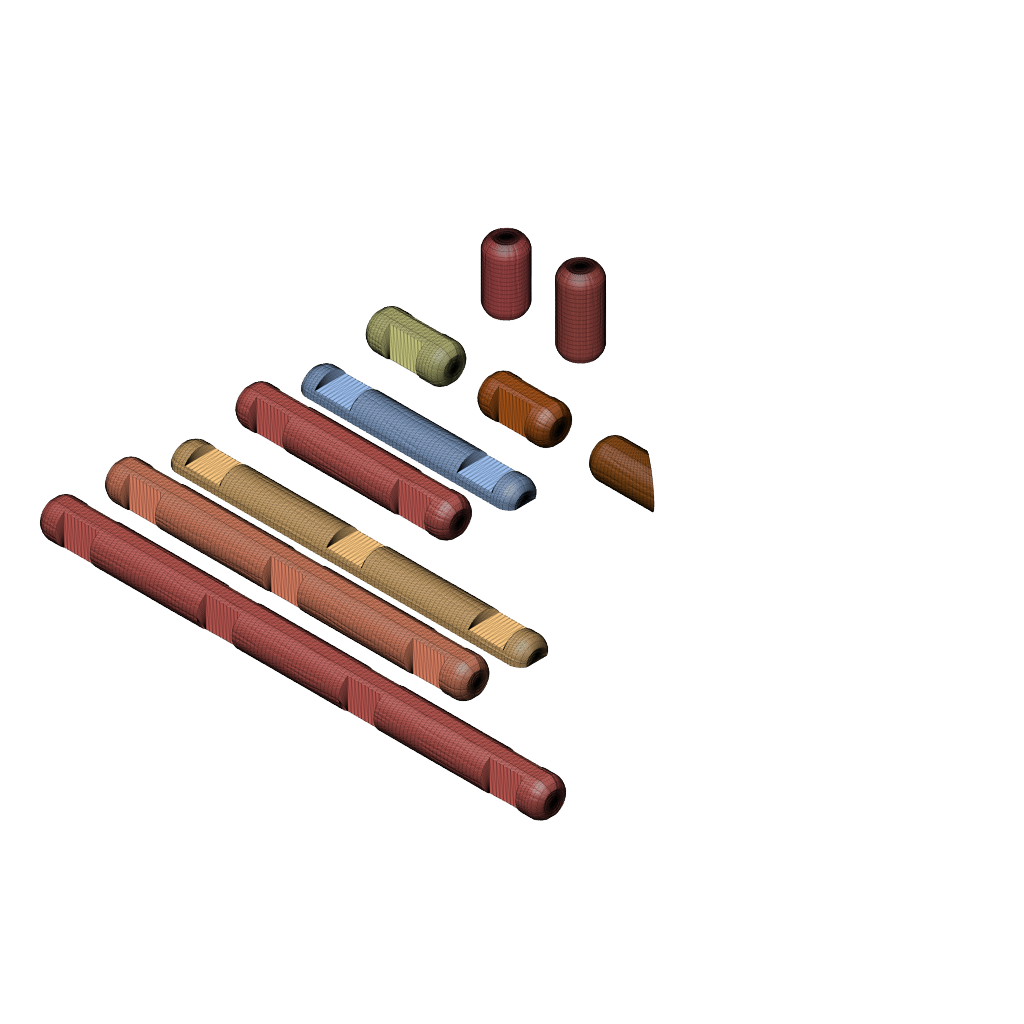
DeadPresidentTreeSections_ball_end_round (Autodesk Fusion 360 design; units mm, degrees)
part number: 2026-11-17-20-53-16-767
part number: 2026-11-17-20-53-16-854
part number: 2026-11-17-20-53-17-063
part number: 2026-11-17-20-53-17-313
part number: 2026-11-17-20-53-17-579
part number: 2026-11-17-20-53-17-888
part number: 2026-11-17-20-53-18-275
part number: 2026-11-17-20-53-18-680
part number: 2026-11-17-20-53-19-149
part number: 2026-11-17-20-53-19-560
part number: 2026-11-17-20-53-19-708
Autodesk Fusion 360 part; units mm, degrees
sketch "Section" plane through (0, 0, 0) normal (1, 0, 0) x (0, 0, -1) in component "log_1insert_1-5_8_rounded"
  circle A0 centre (-9.125, 0) radius 9.525
  dimension "d15" = 9.125
  dimension "d16" = 19.05
  constraint horizontal origin A0.centre
  measures "d15" horizontal distance of origin A0.centre
  measures "d16" diameter of A0
extrude "Log" add sketch "Section" along normal blind 41.275 makes body 1 in component "log_1insert_1-5_8_rounded"
fillet "Rounded ends" radius 4 2 edges at (41.275, -3.4444, 18.0054) (0, -3.4444, 18.0054) on bodies 1 in component "log_1insert_1-5_8_rounded"
sketch "Flats" plane through (0, 0, 0) normal (1, 0, 0) x (0, 0, -1) in component "log_1insert_1-5_8_rounded"
  line L0 (0.8, -11.525) -> (0.8, 11.525)
  line L1 (0.8, 11.525) -> (0, 11.525)
  line L2 (0, 11.525) -> (0, -11.525)
  line L3 (0, -11.525) -> (0.8, -11.525)
  line L4 (-18.25, -11.525) -> (-18.25, 11.525)
  line L5 (-18.25, 11.525) -> (-20.05, 11.525)
  line L6 (-20.05, 11.525) -> (-20.05, -11.525)
  line L7 (-20.05, -11.525) -> (-18.25, -11.525)
  dimension "d21" = 11.525
  dimension "d22" = 0.8
  dimension "d23" = 11.525
  dimension "d24" = 11.525
  dimension "d25" = 18.25
  dimension "d26" = 11.525
  dimension "d27" = 20.05
  constraint vertical L0
  constraint horizontal L1
  constraint vertical L2
  constraint horizontal L3
  constraint vertical origin L1.end
  constraint vertical L4
  constraint horizontal L5
  constraint vertical L6
  constraint horizontal L7
  measures "d21" vertical distance of origin L0.start
  measures "d22" horizontal distance of origin L0.start
  measures "d23" vertical distance of origin L1.end
  measures "d24" vertical distance of origin L4.start
  measures "d25" horizontal distance of origin L4.start
  measures "d26" vertical distance of origin L5.end
  measures "d27" horizontal distance of origin L5.end
extrude "Flats (1)" cut sketch "Flats" along normal blind 41.275 bodies 1 in component "log_1insert_1-5_8_rounded"
sketch "Notch" plane through (0, 0, 0) normal (0, 0, 1) x (1, 0, 0) in component "log_1insert_1-5_8_rounded"
  line L0 (11.3125, 4.7625) -> (29.9625, 4.7625)
  line L1 (29.9625, 4.7625) -> (29.9625, 11.525)
  line L2 (29.9625, 11.525) -> (11.3125, 11.525)
  line L3 (11.3125, 11.525) -> (11.3125, 4.7625)
  line L4 (11.3125, -4.7625) -> (29.9625, -4.7625)
  line L5 (29.9625, -4.7625) -> (29.9625, -11.525)
  line L6 (29.9625, -11.525) -> (11.3125, -11.525)
  line L7 (11.3125, -11.525) -> (11.3125, -4.7625)
  dimension "d30" = 11.3125
  dimension "d31" = 4.7625
  dimension "d32" = 29.9625
  dimension "d33" = 11.525
  dimension "d34" = 11.3125
  dimension "d35" = 4.7625
  dimension "d36" = 29.9625
  dimension "d37" = 11.525
  constraint horizontal L0
  constraint vertical L1
  constraint horizontal L2
  constraint vertical L3
  constraint horizontal L4
  constraint vertical L5
  constraint horizontal L6
  constraint vertical L7
  measures "d30" horizontal distance of origin L0.start
  measures "d31" vertical distance of origin L0.start
  measures "d32" horizontal distance of origin L1.end
  measures "d33" vertical distance of origin L1.end
  measures "d34" horizontal distance of origin L4.start
  measures "d35" vertical distance of origin L4.start
  measures "d36" horizontal distance of origin L5.end
  measures "d37" vertical distance of origin L5.end
extrude "Notch cut" cut sketch "Notch" along normal blind 21.05 bodies 1 in component "log_1insert_1-5_8_rounded"
pattern_linear "Notch pattern" count 2 spacing 0.001 along (1, 0, 0) count 3 spacing 0 along (1, 0, 0) of "Notch cut" in component "log_1insert_1-5_8_rounded"
other "Base Mesh Feature1" in component "log_1insert_1-5_8_rounded"
sketch "Section (2)" plane through (0, 0, 0) normal (1, 0, 0) x (0, 0, -1) in component "log_1insert_1-1_2_round_rounded"
  circle A0 centre (-9.125, 0) radius 9.525
  dimension "d48" = 9.125
  dimension "d49" = 19.05
  constraint horizontal origin A0.centre
  measures "d48" horizontal distance of origin A0.centre
  measures "d49" diameter of A0
extrude "Log'" add sketch "Section (2)" along normal blind 38.1 separate body makes body 2 in component "log_1insert_1-1_2_round_rounded"
fillet "Rounded ends'" radius 4 2 edges at (38.1, -3.4444, 18.0054) (0, -3.4444, 18.0054) on bodies 2 in component "log_1insert_1-1_2_round_rounded"
sketch "Flats (2)" plane through (0, 0, 0) normal (1, 0, 0) x (0, 0, -1) in component "log_1insert_1-1_2_round_rounded"
  line L0 (0.8, -11.525) -> (0.8, 11.525)
  line L1 (0.8, 11.525) -> (0, 11.525)
  line L2 (0, 11.525) -> (0, -11.525)
  line L3 (0, -11.525) -> (0.8, -11.525)
  line L4 (-18.25, -11.525) -> (-18.25, 11.525)
  line L5 (-18.25, 11.525) -> (-20.05, 11.525)
  line L6 (-20.05, 11.525) -> (-20.05, -11.525)
  line L7 (-20.05, -11.525) -> (-18.25, -11.525)
  dimension "d54" = 11.525
  dimension "d55" = 0.8
  dimension "d56" = 11.525
  dimension "d57" = 11.525
  dimension "d58" = 18.25
  dimension "d59" = 11.525
  dimension "d60" = 20.05
  constraint vertical L0
  constraint horizontal L1
  constraint vertical L2
  constraint horizontal L3
  constraint vertical origin L1.end
  constraint vertical L4
  constraint horizontal L5
  constraint vertical L6
  constraint horizontal L7
  measures "d54" vertical distance of origin L0.start
  measures "d55" horizontal distance of origin L0.start
  measures "d56" vertical distance of origin L1.end
  measures "d57" vertical distance of origin L4.start
  measures "d58" horizontal distance of origin L4.start
  measures "d59" vertical distance of origin L5.end
  measures "d60" horizontal distance of origin L5.end
extrude "Flats (1)'" cut sketch "Flats (2)" along normal blind 38.1 bodies 2 in component "log_1insert_1-1_2_round_rounded"
sketch "Notch (2)" plane through (0, 0, 0) normal (0, 0, 1) x (1, 0, 0) in component "log_1insert_1-1_2_round_rounded"
  line L0 (9.725, 4.7625) -> (28.375, 4.7625)
  line L1 (28.375, 4.7625) -> (28.375, 11.525)
  line L2 (28.375, 11.525) -> (9.725, 11.525)
  line L3 (9.725, 11.525) -> (9.725, 4.7625)
  line L4 (9.725, -4.7625) -> (28.375, -4.7625)
  line L5 (28.375, -4.7625) -> (28.375, -11.525)
  line L6 (28.375, -11.525) -> (9.725, -11.525)
  line L7 (9.725, -11.525) -> (9.725, -4.7625)
  dimension "d63" = 9.725
  dimension "d64" = 4.7625
  dimension "d65" = 28.375
  dimension "d66" = 11.525
  dimension "d67" = 9.725
  dimension "d68" = 4.7625
  dimension "d69" = 28.375
  dimension "d70" = 11.525
  constraint horizontal L0
  constraint vertical L1
  constraint horizontal L2
  constraint vertical L3
  constraint horizontal L4
  constraint vertical L5
  constraint horizontal L6
  constraint vertical L7
  measures "d63" horizontal distance of origin L0.start
  measures "d64" vertical distance of origin L0.start
  measures "d65" horizontal distance of origin L1.end
  measures "d66" vertical distance of origin L1.end
  measures "d67" horizontal distance of origin L4.start
  measures "d68" vertical distance of origin L4.start
  measures "d69" horizontal distance of origin L5.end
  measures "d70" vertical distance of origin L5.end
extrude "Notch cut'" cut sketch "Notch (2)" along normal blind 21.05 bodies 2 in component "log_1insert_1-1_2_round_rounded"
pattern_linear "Notch pattern'" count 2 spacing 0.001 along (1, 0, 0) count 3 spacing 0 along (1, 0, 0) of "Notch cut'" in component "log_1insert_1-1_2_round_rounded"
other "Base Mesh Feature1'" in component "log_1insert_1-1_2_round_rounded"
sketch "Section (3)" plane through (0, 0, 0) normal (1, 0, 0) x (0, 0, -1) in component "log_2insert_4-1_2_rounded"
  circle A0 centre (-9.125, 0) radius 9.525
  dimension "d81" = 9.125
  dimension "d82" = 19.05
  constraint horizontal origin A0.centre
  measures "d81" horizontal distance of origin A0.centre
  measures "d82" diameter of A0
extrude "Log''" add sketch "Section (3)" along normal blind 114.3 separate body makes body 3 in component "log_2insert_4-1_2_rounded"
fillet "Rounded ends''" radius 4 2 edges at (114.3, -3.4444, 18.0054) (0, -3.4444, 18.0054) on bodies 3 in component "log_2insert_4-1_2_rounded"
sketch "Flats (3)" plane through (0, 0, 0) normal (1, 0, 0) x (0, 0, -1) in component "log_2insert_4-1_2_rounded"
  line L0 (0.8, -11.525) -> (0.8, 11.525)
  line L1 (0.8, 11.525) -> (0, 11.525)
  line L2 (0, 11.525) -> (0, -11.525)
  line L3 (0, -11.525) -> (0.8, -11.525)
  line L4 (-18.25, -11.525) -> (-18.25, 11.525)
  line L5 (-18.25, 11.525) -> (-20.05, 11.525)
  line L6 (-20.05, 11.525) -> (-20.05, -11.525)
  line L7 (-20.05, -11.525) -> (-18.25, -11.525)
  dimension "d87" = 11.525
  dimension "d88" = 0.8
  dimension "d89" = 11.525
  dimension "d90" = 11.525
  dimension "d91" = 18.25
  dimension "d92" = 11.525
  dimension "d93" = 20.05
  constraint vertical L0
  constraint horizontal L1
  constraint vertical L2
  constraint horizontal L3
  constraint vertical origin L1.end
  constraint vertical L4
  constraint horizontal L5
  constraint vertical L6
  constraint horizontal L7
  measures "d87" vertical distance of origin L0.start
  measures "d88" horizontal distance of origin L0.start
  measures "d89" vertical distance of origin L1.end
  measures "d90" vertical distance of origin L4.start
  measures "d91" horizontal distance of origin L4.start
  measures "d92" vertical distance of origin L5.end
  measures "d93" horizontal distance of origin L5.end
extrude "Flats (1)''" cut sketch "Flats (3)" along normal blind 114.3 bodies 3 in component "log_2insert_4-1_2_rounded"
sketch "Notch (3)" plane through (0, 0, 0) normal (0, 0, 1) x (1, 0, 0) in component "log_2insert_4-1_2_rounded"
  line L0 (9.725, 4.7625) -> (28.375, 4.7625)
  line L1 (28.375, 4.7625) -> (28.375, 11.525)
  line L2 (28.375, 11.525) -> (9.725, 11.525)
  line L3 (9.725, 11.525) -> (9.725, 4.7625)
  line L4 (9.725, -4.7625) -> (28.375, -4.7625)
  line L5 (28.375, -4.7625) -> (28.375, -11.525)
  line L6 (28.375, -11.525) -> (9.725, -11.525)
  line L7 (9.725, -11.525) -> (9.725, -4.7625)
  dimension "d96" = 9.725
  dimension "d97" = 4.7625
  dimension "d98" = 28.375
  dimension "d99" = 11.525
  dimension "d100" = 9.725
  dimension "d101" = 4.7625
  dimension "d102" = 28.375
  dimension "d103" = 11.525
  constraint horizontal L0
  constraint vertical L1
  constraint horizontal L2
  constraint vertical L3
  constraint horizontal L4
  constraint vertical L5
  constraint horizontal L6
  constraint vertical L7
  measures "d96" horizontal distance of origin L0.start
  measures "d97" vertical distance of origin L0.start
  measures "d98" horizontal distance of origin L1.end
  measures "d99" vertical distance of origin L1.end
  measures "d100" horizontal distance of origin L4.start
  measures "d101" vertical distance of origin L4.start
  measures "d102" horizontal distance of origin L5.end
  measures "d103" vertical distance of origin L5.end
extrude "Notch cut''" cut sketch "Notch (3)" along normal blind 21.05 bodies 3 in component "log_2insert_4-1_2_rounded"
pattern_linear "Notch pattern''" count 2 spacing 76.2 along (1, 0, 0) count 3 spacing 0 along (1, 0, 0) of "Notch cut''" in component "log_2insert_4-1_2_rounded"
other "Base Mesh Feature1''" in component "log_2insert_4-1_2_rounded"
sketch "Section (4)" plane through (0, 0, 0) normal (1, 0, 0) x (0, 0, -1) in component "log_3insert_7-5_8_rounded"
  circle A0 centre (-9.125, 0) radius 9.525
  dimension "d114" = 9.125
  dimension "d115" = 19.05
  constraint horizontal origin A0.centre
  measures "d114" horizontal distance of origin A0.centre
  measures "d115" diameter of A0
extrude "Log'''" add sketch "Section (4)" along normal blind 193.675 separate body makes body 4 in component "log_3insert_7-5_8_rounded"
fillet "Rounded ends'''" radius 4 2 edges at (193.675, -3.4444, 18.0054) (0, -3.4444, 18.0054) on bodies 4 in component "log_3insert_7-5_8_rounded"
sketch "Flats (4)" plane through (0, 0, 0) normal (1, 0, 0) x (0, 0, -1) in component "log_3insert_7-5_8_rounded"
  line L0 (0.8, -11.525) -> (0.8, 11.525)
  line L1 (0.8, 11.525) -> (0, 11.525)
  line L2 (0, 11.525) -> (0, -11.525)
  line L3 (0, -11.525) -> (0.8, -11.525)
  line L4 (-18.25, -11.525) -> (-18.25, 11.525)
  line L5 (-18.25, 11.525) -> (-20.05, 11.525)
  line L6 (-20.05, 11.525) -> (-20.05, -11.525)
  line L7 (-20.05, -11.525) -> (-18.25, -11.525)
  dimension "d120" = 11.525
  dimension "d121" = 0.8
  dimension "d122" = 11.525
  dimension "d123" = 11.525
  dimension "d124" = 18.25
  dimension "d125" = 11.525
  dimension "d126" = 20.05
  constraint vertical L0
  constraint horizontal L1
  constraint vertical L2
  constraint horizontal L3
  constraint vertical origin L1.end
  constraint vertical L4
  constraint horizontal L5
  constraint vertical L6
  constraint horizontal L7
  measures "d120" vertical distance of origin L0.start
  measures "d121" horizontal distance of origin L0.start
  measures "d122" vertical distance of origin L1.end
  measures "d123" vertical distance of origin L4.start
  measures "d124" horizontal distance of origin L4.start
  measures "d125" vertical distance of origin L5.end
  measures "d126" horizontal distance of origin L5.end
extrude "Flats (1)'''" cut sketch "Flats (4)" along normal blind 193.675 bodies 4 in component "log_3insert_7-5_8_rounded"
sketch "Notch (4)" plane through (0, 0, 0) normal (0, 0, 1) x (1, 0, 0) in component "log_3insert_7-5_8_rounded"
  line L0 (11.3125, 4.7625) -> (29.9625, 4.7625)
  line L1 (29.9625, 4.7625) -> (29.9625, 11.525)
  line L2 (29.9625, 11.525) -> (11.3125, 11.525)
  line L3 (11.3125, 11.525) -> (11.3125, 4.7625)
  line L4 (11.3125, -4.7625) -> (29.9625, -4.7625)
  line L5 (29.9625, -4.7625) -> (29.9625, -11.525)
  line L6 (29.9625, -11.525) -> (11.3125, -11.525)
  line L7 (11.3125, -11.525) -> (11.3125, -4.7625)
  dimension "d129" = 11.3125
  dimension "d130" = 4.7625
  dimension "d131" = 29.9625
  dimension "d132" = 11.525
  dimension "d133" = 11.3125
  dimension "d134" = 4.7625
  dimension "d135" = 29.9625
  dimension "d136" = 11.525
  constraint horizontal L0
  constraint vertical L1
  constraint horizontal L2
  constraint vertical L3
  constraint horizontal L4
  constraint vertical L5
  constraint horizontal L6
  constraint vertical L7
  measures "d129" horizontal distance of origin L0.start
  measures "d130" vertical distance of origin L0.start
  measures "d131" horizontal distance of origin L1.end
  measures "d132" vertical distance of origin L1.end
  measures "d133" horizontal distance of origin L4.start
  measures "d134" vertical distance of origin L4.start
  measures "d135" horizontal distance of origin L5.end
  measures "d136" vertical distance of origin L5.end
extrude "Notch cut'''" cut sketch "Notch (4)" along normal blind 21.05 bodies 4 in component "log_3insert_7-5_8_rounded"
pattern_linear "Notch pattern'''" count 3 spacing 76.2 along (1, 0, 0) count 3 spacing 0 along (1, 0, 0) of "Notch cut'''" in component "log_3insert_7-5_8_rounded"
other "Base Mesh Feature1'''" in component "log_3insert_7-5_8_rounded"
sketch "Section (5)" plane through (0, 0, 0) normal (1, 0, 0) x (0, 0, -1) in component "log_4insert_10-5_8_rounded"
  circle A0 centre (-9.125, 0) radius 9.525
  dimension "d147" = 9.125
  dimension "d148" = 19.05
  constraint horizontal origin A0.centre
  measures "d147" horizontal distance of origin A0.centre
  measures "d148" diameter of A0
extrude "Log''''" add sketch "Section (5)" along normal blind 269.875 separate body makes body 5 in component "log_4insert_10-5_8_rounded"
fillet "Rounded ends''''" radius 4 2 edges at (269.875, -3.4444, 18.0054) (0, -3.4444, 18.0054) on bodies 5 in component "log_4insert_10-5_8_rounded"
sketch "Flats (5)" plane through (0, 0, 0) normal (1, 0, 0) x (0, 0, -1) in component "log_4insert_10-5_8_rounded"
  line L0 (0.8, -11.525) -> (0.8, 11.525)
  line L1 (0.8, 11.525) -> (0, 11.525)
  line L2 (0, 11.525) -> (0, -11.525)
  line L3 (0, -11.525) -> (0.8, -11.525)
  line L4 (-18.25, -11.525) -> (-18.25, 11.525)
  line L5 (-18.25, 11.525) -> (-20.05, 11.525)
  line L6 (-20.05, 11.525) -> (-20.05, -11.525)
  line L7 (-20.05, -11.525) -> (-18.25, -11.525)
  dimension "d153" = 11.525
  dimension "d154" = 0.8
  dimension "d155" = 11.525
  dimension "d156" = 11.525
  dimension "d157" = 18.25
  dimension "d158" = 11.525
  dimension "d159" = 20.05
  constraint vertical L0
  constraint horizontal L1
  constraint vertical L2
  constraint horizontal L3
  constraint vertical origin L1.end
  constraint vertical L4
  constraint horizontal L5
  constraint vertical L6
  constraint horizontal L7
  measures "d153" vertical distance of origin L0.start
  measures "d154" horizontal distance of origin L0.start
  measures "d155" vertical distance of origin L1.end
  measures "d156" vertical distance of origin L4.start
  measures "d157" horizontal distance of origin L4.start
  measures "d158" vertical distance of origin L5.end
  measures "d159" horizontal distance of origin L5.end
extrude "Flats (1)''''" cut sketch "Flats (5)" along normal blind 269.875 bodies 5 in component "log_4insert_10-5_8_rounded"
sketch "Notch (5)" plane through (0, 0, 0) normal (0, 0, 1) x (1, 0, 0) in component "log_4insert_10-5_8_rounded"
  line L0 (11.3125, 4.7625) -> (29.9625, 4.7625)
  line L1 (29.9625, 4.7625) -> (29.9625, 11.525)
  line L2 (29.9625, 11.525) -> (11.3125, 11.525)
  line L3 (11.3125, 11.525) -> (11.3125, 4.7625)
  line L4 (11.3125, -4.7625) -> (29.9625, -4.7625)
  line L5 (29.9625, -4.7625) -> (29.9625, -11.525)
  line L6 (29.9625, -11.525) -> (11.3125, -11.525)
  line L7 (11.3125, -11.525) -> (11.3125, -4.7625)
  dimension "d162" = 11.3125
  dimension "d163" = 4.7625
  dimension "d164" = 29.9625
  dimension "d165" = 11.525
  dimension "d166" = 11.3125
  dimension "d167" = 4.7625
  dimension "d168" = 29.9625
  dimension "d169" = 11.525
  constraint horizontal L0
  constraint vertical L1
  constraint horizontal L2
  constraint vertical L3
  constraint horizontal L4
  constraint vertical L5
  constraint horizontal L6
  constraint vertical L7
  measures "d162" horizontal distance of origin L0.start
  measures "d163" vertical distance of origin L0.start
  measures "d164" horizontal distance of origin L1.end
  measures "d165" vertical distance of origin L1.end
  measures "d166" horizontal distance of origin L4.start
  measures "d167" vertical distance of origin L4.start
  measures "d168" horizontal distance of origin L5.end
  measures "d169" vertical distance of origin L5.end
extrude "Notch cut''''" cut sketch "Notch (5)" along normal blind 21.05 bodies 5 in component "log_4insert_10-5_8_rounded"
pattern_linear "Notch pattern''''" count 4 spacing 76.2 along (1, 0, 0) count 3 spacing 0 along (1, 0, 0) of "Notch cut''''" in component "log_4insert_10-5_8_rounded"
other "Base Mesh Feature1''''" in component "log_4insert_10-5_8_rounded"
sketch "Section (6)" plane through (0, 0, 0) normal (1, 0, 0) x (0, 0, -1) in component "base_log_4-1_2_rounded"
  circle A0 centre (0, 0) radius 9.525
  dimension "d180" = 19.05
  constraint coincident A0.centre origin
  measures "d180" diameter of A0
extrude "Log'''''" add sketch "Section (6)" along normal blind 114.3 separate body makes body 6 in component "base_log_4-1_2_rounded"
fillet "Rounded ends'''''" radius 4 2 edges at (114.3, -3.4444, 8.8804) (0, -3.4444, 8.8804) on bodies 6 in component "base_log_4-1_2_rounded"
sketch "Bed and side flats" plane through (0, 0, 0) normal (1, 0, 0) x (0, 0, -1) in component "base_log_4-1_2_rounded"
  line L0 (10.525, -11.525) -> (10.525, 11.525)
  line L1 (10.525, 11.525) -> (0, 11.525)
  line L2 (0, 11.525) -> (0, -11.525)
  line L3 (0, -11.525) -> (10.525, -11.525)
  line L4 (1, 9.125) -> (1, 11.525)
  line L5 (1, 11.525) -> (-20.05, 11.525)
  line L6 (-20.05, 11.525) -> (-20.05, 9.125)
  line L7 (-20.05, 9.125) -> (1, 9.125)
  line L8 (1, -9.125) -> (1, -11.525)
  line L9 (1, -11.525) -> (-20.05, -11.525)
  line L10 (-20.05, -11.525) -> (-20.05, -9.125)
  line L11 (-20.05, -9.125) -> (1, -9.125)
  dimension "d185" = 11.525
  dimension "d186" = 10.525
  dimension "d187" = 11.525
  dimension "d188" = 9.125
  dimension "d189" = 1
  dimension "d190" = 11.525
  dimension "d191" = 20.05
  dimension "d192" = 9.125
  dimension "d193" = 1
  dimension "d194" = 11.525
  dimension "d195" = 20.05
  constraint vertical L0
  constraint horizontal L1
  constraint vertical L2
  constraint horizontal L3
  constraint vertical origin L1.end
  constraint vertical L4
  constraint horizontal L5
  constraint vertical L6
  constraint horizontal L7
  constraint vertical L8
  constraint horizontal L9
  constraint vertical L10
  constraint horizontal L11
  measures "d185" vertical distance of origin L0.start
  measures "d186" horizontal distance of origin L0.start
  measures "d187" vertical distance of origin L1.end
  measures "d188" vertical distance of origin L4.start
  measures "d189" horizontal distance of origin L4.start
  measures "d190" vertical distance of origin L5.end
  measures "d191" horizontal distance of origin L5.end
  measures "d192" vertical distance of origin L8.start
  measures "d193" horizontal distance of origin L8.start
  measures "d194" vertical distance of origin L9.end
  measures "d195" horizontal distance of origin L9.end
extrude "Bed and side flats (1)" cut sketch "Bed and side flats" along normal blind 114.3 bodies 6 in component "base_log_4-1_2_rounded"
sketch "Notch (6)" plane through (0, 0, 0) normal (0, 1, 0) x (1, 0, 0) in component "base_log_4-1_2_rounded"
  line L0 (9.725, -4.7625) -> (28.375, -4.7625)
  line L1 (28.375, -4.7625) -> (28.375, -10.525)
  line L2 (28.375, -10.525) -> (9.725, -10.525)
  line L3 (9.725, -10.525) -> (9.725, -4.7625)
  dimension "d198" = 9.725
  dimension "d199" = 4.7625
  dimension "d200" = 28.375
  dimension "d201" = 10.525
  constraint horizontal L0
  constraint vertical L1
  constraint horizontal L2
  constraint vertical L3
  measures "d198" horizontal distance of origin L0.start
  measures "d199" vertical distance of origin L0.start
  measures "d200" horizontal distance of origin L1.end
  measures "d201" vertical distance of origin L1.end
extrude "Notch cut'''''" cut sketch "Notch (6)" along normal mid plane 21.05 bodies 6 in component "base_log_4-1_2_rounded"
pattern_linear "Notch pattern'''''" count 2 spacing 76.2 along (1, 0, 0) count 3 spacing 0 along (1, 0, 0) of "Notch cut'''''" in component "base_log_4-1_2_rounded"
other "Base Mesh Feature1'''''" in component "base_log_4-1_2_rounded"
sketch "Section (7)" plane through (0, 0, 0) normal (1, 0, 0) x (0, 0, -1) in component "base_log_7-1_2_rounded"
  circle A0 centre (0, 0) radius 9.525
  dimension "d212" = 19.05
  constraint coincident A0.centre origin
  measures "d212" diameter of A0
extrude "Log''''''" add sketch "Section (7)" along normal blind 190.5 separate body makes body 7 in component "base_log_7-1_2_rounded"
fillet "Rounded ends''''''" radius 4 2 edges at (190.5, -3.4444, 8.8804) (0, -3.4444, 8.8804) on bodies 7 in component "base_log_7-1_2_rounded"
sketch "Bed and side flats (2)" plane through (0, 0, 0) normal (1, 0, 0) x (0, 0, -1) in component "base_log_7-1_2_rounded"
  line L0 (10.525, -11.525) -> (10.525, 11.525)
  line L1 (10.525, 11.525) -> (0, 11.525)
  line L2 (0, 11.525) -> (0, -11.525)
  line L3 (0, -11.525) -> (10.525, -11.525)
  line L4 (1, 9.125) -> (1, 11.525)
  line L5 (1, 11.525) -> (-20.05, 11.525)
  line L6 (-20.05, 11.525) -> (-20.05, 9.125)
  line L7 (-20.05, 9.125) -> (1, 9.125)
  line L8 (1, -9.125) -> (1, -11.525)
  line L9 (1, -11.525) -> (-20.05, -11.525)
  line L10 (-20.05, -11.525) -> (-20.05, -9.125)
  line L11 (-20.05, -9.125) -> (1, -9.125)
  dimension "d217" = 11.525
  dimension "d218" = 10.525
  dimension "d219" = 11.525
  dimension "d220" = 9.125
  dimension "d221" = 1
  dimension "d222" = 11.525
  dimension "d223" = 20.05
  dimension "d224" = 9.125
  dimension "d225" = 1
  dimension "d226" = 11.525
  dimension "d227" = 20.05
  constraint vertical L0
  constraint horizontal L1
  constraint vertical L2
  constraint horizontal L3
  constraint vertical origin L1.end
  constraint vertical L4
  constraint horizontal L5
  constraint vertical L6
  constraint horizontal L7
  constraint vertical L8
  constraint horizontal L9
  constraint vertical L10
  constraint horizontal L11
  measures "d217" vertical distance of origin L0.start
  measures "d218" horizontal distance of origin L0.start
  measures "d219" vertical distance of origin L1.end
  measures "d220" vertical distance of origin L4.start
  measures "d221" horizontal distance of origin L4.start
  measures "d222" vertical distance of origin L5.end
  measures "d223" horizontal distance of origin L5.end
  measures "d224" vertical distance of origin L8.start
  measures "d225" horizontal distance of origin L8.start
  measures "d226" vertical distance of origin L9.end
  measures "d227" horizontal distance of origin L9.end
extrude "Bed and side flats (1)'" cut sketch "Bed and side flats (2)" along normal blind 190.5 bodies 7 in component "base_log_7-1_2_rounded"
sketch "Notch (7)" plane through (0, 0, 0) normal (0, 1, 0) x (1, 0, 0) in component "base_log_7-1_2_rounded"
  line L0 (9.725, -4.7625) -> (28.375, -4.7625)
  line L1 (28.375, -4.7625) -> (28.375, -10.525)
  line L2 (28.375, -10.525) -> (9.725, -10.525)
  line L3 (9.725, -10.525) -> (9.725, -4.7625)
  dimension "d230" = 9.725
  dimension "d231" = 4.7625
  dimension "d232" = 28.375
  dimension "d233" = 10.525
  constraint horizontal L0
  constraint vertical L1
  constraint horizontal L2
  constraint vertical L3
  measures "d230" horizontal distance of origin L0.start
  measures "d231" vertical distance of origin L0.start
  measures "d232" horizontal distance of origin L1.end
  measures "d233" vertical distance of origin L1.end
extrude "Notch cut''''''" cut sketch "Notch (7)" along normal mid plane 21.05 bodies 7 in component "base_log_7-1_2_rounded"
pattern_linear "Notch pattern''''''" count 3 spacing 76.2 along (1, 0, 0) count 3 spacing 0 along (1, 0, 0) of "Notch cut''''''" in component "base_log_7-1_2_rounded"
other "Base Mesh Feature1''''''" in component "base_log_7-1_2_rounded"
sketch "Section (8)" plane through (0, 0, 0) normal (1, 0, 0) x (0, 0, -1) in component "beveled_end_1-1_2_rounded"
  circle A0 centre (-9.125, 0) radius 9.525
  dimension "d242" = 9.125
  dimension "d243" = 19.05
  constraint horizontal origin A0.centre
  measures "d242" horizontal distance of origin A0.centre
  measures "d243" diameter of A0
extrude "Log'''''''" add sketch "Section (8)" along normal blind 38.1 separate body makes body 8 in component "beveled_end_1-1_2_rounded"
fillet "Rounded ends'''''''" radius 4 1 edges at (0, -3.4444, 18.0054) on bodies 8 in component "beveled_end_1-1_2_rounded"
sketch "Flats (6)" plane through (0, 0, 0) normal (1, 0, 0) x (0, 0, -1) in component "beveled_end_1-1_2_rounded"
  line L0 (0.8, -11.525) -> (0.8, 11.525)
  line L1 (0.8, 11.525) -> (0, 11.525)
  line L2 (0, 11.525) -> (0, -11.525)
  line L3 (0, -11.525) -> (0.8, -11.525)
  line L4 (-18.25, -11.525) -> (-18.25, 11.525)
  line L5 (-18.25, 11.525) -> (-20.05, 11.525)
  line L6 (-20.05, 11.525) -> (-20.05, -11.525)
  line L7 (-20.05, -11.525) -> (-18.25, -11.525)
  dimension "d248" = 11.525
  dimension "d249" = 0.8
  dimension "d250" = 11.525
  dimension "d251" = 11.525
  dimension "d252" = 18.25
  dimension "d253" = 11.525
  dimension "d254" = 20.05
  constraint vertical L0
  constraint horizontal L1
  constraint vertical L2
  constraint horizontal L3
  constraint vertical origin L1.end
  constraint vertical L4
  constraint horizontal L5
  constraint vertical L6
  constraint horizontal L7
  measures "d248" vertical distance of origin L0.start
  measures "d249" horizontal distance of origin L0.start
  measures "d250" vertical distance of origin L1.end
  measures "d251" vertical distance of origin L4.start
  measures "d252" horizontal distance of origin L4.start
  measures "d253" vertical distance of origin L5.end
  measures "d254" horizontal distance of origin L5.end
extrude "Flats (1)'''''" cut sketch "Flats (6)" along normal blind 38.1 bodies 8 in component "beveled_end_1-1_2_rounded"
sketch "Slant" plane through (0, 0, 0) normal (0, 0, 1) x (1, 0, 0) in component "beveled_end_1-1_2_rounded"
  line L0 (38.1, -9.525) -> (38.1, 9.525)
  line L1 (38.1, 9.525) -> (14.5752, 9.525)
  line L2 (14.5752, 9.525) -> (38.1, -9.525)
  dimension "d257" = 38.1
  dimension "d258" = 9.525
  dimension "d259" = 9.525
  dimension "d260" = 14.5752
  constraint vertical L0.start L0.end
  constraint horizontal L0.end L1.end
  measures "d257" horizontal distance of origin L0.start
  measures "d258" vertical distance of origin L0.start
  measures "d259" vertical distance of origin L0.end
  measures "d260" horizontal distance of origin L1.end
extrude "Slanted end" cut sketch "Slant" along normal blind 21.05 bodies 8 in component "beveled_end_1-1_2_rounded"
other "Base Mesh Feature1'''''''" in component "beveled_end_1-1_2_rounded"
sketch "Section (9)" plane through (0, 0, 0) normal (0, 0, 1) x (1, 0, 0) in component "solid_log_1-3_8_rounded"
  circle A0 centre (9.525, 9.525) radius 9.525
  dimension "d264" = 9.525
  dimension "d265" = 9.525
  dimension "d266" = 19.05
  measures "d264" horizontal distance of origin A0.centre
  measures "d265" vertical distance of origin A0.centre
  measures "d266" diameter of A0
extrude "Log''''''''" add sketch "Section (9)" along normal blind 34.925 separate body makes body 9 in component "solid_log_1-3_8_rounded"
fillet "Rounded ends''''''''" radius 4 2 edges at (0.6446, 6.0806, 34.925) (0.6446, 6.0806, 0) on bodies 9 in component "solid_log_1-3_8_rounded"
other "Base Mesh Feature1''''''''" in component "solid_log_1-3_8_rounded"
sketch "Section (10)" plane through (0, 0, 0) normal (0, 0, 1) x (1, 0, 0) in component "solid_log_1-5_8_rounded"
  circle A0 centre (9.525, 9.525) radius 9.525
  dimension "d272" = 9.525
  dimension "d273" = 9.525
  dimension "d274" = 19.05
  measures "d272" horizontal distance of origin A0.centre
  measures "d273" vertical distance of origin A0.centre
  measures "d274" diameter of A0
extrude "Log'''''''''" add sketch "Section (10)" along normal blind 41.275 separate body makes body 10 in component "solid_log_1-5_8_rounded"
fillet "Rounded ends'''''''''" radius 4 2 edges at (0.6446, 6.0806, 41.275) (0.6446, 6.0806, 0) on bodies 10 in component "solid_log_1-5_8_rounded"
other "Base Mesh Feature1'''''''''" in component "solid_log_1-5_8_rounded"
component "log_1insert_1-5_8_rounded" placed x (1, 0, 0) y (0, 1, 0) z (0, 0, 1) at (0, 175, 0)
component "log_1insert_1-1_2_round_rounded" placed x (1, 0, 0) y (0, 1, 0) z (0, 0, 1) at (60, 175, 0)
component "log_2insert_4-1_2_rounded" placed x (1, 0, 0) y (0, 1, 0) z (0, 0, 1) at (0, 105, 0)
component "log_3insert_7-5_8_rounded" placed x (1, 0, 0) y (0, 1, 0) z (0, 0, 1) at (0, 35, 0)
component "log_4insert_10-5_8_rounded" placed x (1, 0, 0) y (0, 1, 0) z (0, 0, 1) at (0, 0, 0)
component "base_log_4-1_2_rounded" placed x (1, 0, 0) y (0, 1, 0) z (0, 0, 1) at (0, 140, 0)
component "base_log_7-1_2_rounded" placed x (1, 0, 0) y (0, 1, 0) z (0, 0, 1) at (0, 70, 0)
component "beveled_end_1-1_2_rounded" placed x (1, 0, 0) y (0, 1, 0) z (0, 0, 1) at (120, 175, 0)
component "solid_log_1-3_8_rounded" placed x (1, 0, 0) y (0, 1, 0) z (0, 0, 1) at (10, 215, 0)
component "solid_log_1-5_8_rounded" placed x (1, 0, 0) y (0, 1, 0) z (0, 0, 1) at (50, 215, 0)
hidden bodies 1 2 3 4 5 6 7 8 9 10
equation "LogDia = 0.75 in" comment "Log diameter (across the flats of an octagonal log)"
equation "NotchDepth = 0.1875 in" comment "Notch depth, each side of a log"
equation "NotchCenters = 3 in" comment "Spacing between notch centres"
equation "Clearance = 0.2 mm" comment "Fit clearance per side. Try 0.3 mm for PETG"
equation "PrintFlat = 0.8 mm" comment "Total width taken off a log, as an equal flat on each side; one is the bed side"
equation "MateWidth = LogDia - PrintFlat" comment "Width of a log, base log or gable where it sits in a notch"
equation "NotchWidth = MateWidth + 2 * Clearance" comment "Notch width (mating width plus clearance on each side)"
equation "CourseRise = LogDia - 2 * NotchDepth" comment "Height gained per crossing course"
equation "BaseLogHeight = LogDia / 2" comment "Base-log height (a log split in half along its axis)"
equation "EndRadius = 4 mm" comment "Radius of the rounded log ends"
equation "L1a_Length = 1.625 in" comment "Overall length"
equation "L1a_Notches = 1" comment "Number of notch positions"
equation "L1a_FirstNotch = ( L1a_Length - ( L1a_Notches - 1 ) * NotchCenters ) / 2" comment "Centre of the first notch (keeps the row of notches centred)"
equation "L1a_NotchStep = NotchCenters * min(1; L1a_Notches - 1) + 0.001 mm * ( 1 - min(1; L1a_Notches - 1) )" comment "Pattern step: NotchCenters, or about zero when there is only one notch"
equation "d15 = LogDia / 2 - PrintFlat / 2"
equation "d16 = LogDia"
equation "d17 = L1a_Length"
equation "d20 = EndRadius"
equation "d21 = LogDia / 2 + 2 mm"
equation "d22 = PrintFlat"
equation "d23 = LogDia / 2 + 2 mm"
equation "d24 = LogDia / 2 + 2 mm"
equation "d25 = MateWidth"
equation "d26 = LogDia / 2 + 2 mm"
equation "d27 = LogDia + 1 mm"
equation "d28 = L1a_Length"
equation "d30 = L1a_FirstNotch - NotchWidth / 2"
equation "d31 = LogDia / 2 - NotchDepth"
equation "d32 = L1a_FirstNotch + NotchWidth / 2"
equation "d33 = LogDia / 2 + 2 mm"
equation "d34 = L1a_FirstNotch - NotchWidth / 2"
equation "d35 = LogDia / 2 - NotchDepth"
equation "d36 = L1a_FirstNotch + NotchWidth / 2"
equation "d37 = LogDia / 2 + 2 mm"
equation "d38 = LogDia + 2 mm"
equation "d40 = max(L1a_Notches; 2)"
equation "d42 = L1a_NotchStep"
equation "L1b_Length = 1.5 in" comment "Overall length"
equation "L1b_Notches = 1" comment "Number of notch positions"
equation "L1b_FirstNotch = ( L1b_Length - ( L1b_Notches - 1 ) * NotchCenters ) / 2" comment "Centre of the first notch (keeps the row of notches centred)"
equation "L1b_NotchStep = NotchCenters * min(1; L1b_Notches - 1) + 0.001 mm * ( 1 - min(1; L1b_Notches - 1) )" comment "Pattern step: NotchCenters, or about zero when there is only one notch"
equation "d48 = LogDia / 2 - PrintFlat / 2"
equation "d49 = LogDia"
equation "d50 = L1b_Length"
equation "d53 = EndRadius"
equation "d54 = LogDia / 2 + 2 mm"
equation "d55 = PrintFlat"
equation "d56 = LogDia / 2 + 2 mm"
equation "d57 = LogDia / 2 + 2 mm"
equation "d58 = MateWidth"
equation "d59 = LogDia / 2 + 2 mm"
equation "d60 = LogDia + 1 mm"
equation "d61 = L1b_Length"
equation "d63 = L1b_FirstNotch - NotchWidth / 2"
equation "d64 = LogDia / 2 - NotchDepth"
equation "d65 = L1b_FirstNotch + NotchWidth / 2"
equation "d66 = LogDia / 2 + 2 mm"
equation "d67 = L1b_FirstNotch - NotchWidth / 2"
equation "d68 = LogDia / 2 - NotchDepth"
equation "d69 = L1b_FirstNotch + NotchWidth / 2"
equation "d70 = LogDia / 2 + 2 mm"
equation "d71 = LogDia + 2 mm"
equation "d73 = max(L1b_Notches; 2)"
equation "d75 = L1b_NotchStep"
equation "L2_Length = 4.5 in" comment "Overall length"
equation "L2_Notches = 2" comment "Number of notch positions"
equation "L2_FirstNotch = ( L2_Length - ( L2_Notches - 1 ) * NotchCenters ) / 2" comment "Centre of the first notch (keeps the row of notches centred)"
equation "L2_NotchStep = NotchCenters * min(1; L2_Notches - 1) + 0.001 mm * ( 1 - min(1; L2_Notches - 1) )" comment "Pattern step: NotchCenters, or about zero when there is only one notch"
equation "d81 = LogDia / 2 - PrintFlat / 2"
equation "d82 = LogDia"
equation "d83 = L2_Length"
equation "d86 = EndRadius"
equation "d87 = LogDia / 2 + 2 mm"
equation "d88 = PrintFlat"
equation "d89 = LogDia / 2 + 2 mm"
equation "d90 = LogDia / 2 + 2 mm"
equation "d91 = MateWidth"
equation "d92 = LogDia / 2 + 2 mm"
equation "d93 = LogDia + 1 mm"
equation "d94 = L2_Length"
equation "d96 = L2_FirstNotch - NotchWidth / 2"
equation "d97 = LogDia / 2 - NotchDepth"
equation "d98 = L2_FirstNotch + NotchWidth / 2"
equation "d99 = LogDia / 2 + 2 mm"
equation "d100 = L2_FirstNotch - NotchWidth / 2"
equation "d101 = LogDia / 2 - NotchDepth"
equation "d102 = L2_FirstNotch + NotchWidth / 2"
equation "d103 = LogDia / 2 + 2 mm"
equation "d104 = LogDia + 2 mm"
equation "d106 = max(L2_Notches; 2)"
equation "d108 = L2_NotchStep"
equation "L3_Length = 7.625 in" comment "Overall length"
equation "L3_Notches = 3" comment "Number of notch positions"
equation "L3_FirstNotch = ( L3_Length - ( L3_Notches - 1 ) * NotchCenters ) / 2" comment "Centre of the first notch (keeps the row of notches centred)"
equation "L3_NotchStep = NotchCenters * min(1; L3_Notches - 1) + 0.001 mm * ( 1 - min(1; L3_Notches - 1) )" comment "Pattern step: NotchCenters, or about zero when there is only one notch"
equation "d114 = LogDia / 2 - PrintFlat / 2"
equation "d115 = LogDia"
equation "d116 = L3_Length"
equation "d119 = EndRadius"
equation "d120 = LogDia / 2 + 2 mm"
equation "d121 = PrintFlat"
equation "d122 = LogDia / 2 + 2 mm"
equation "d123 = LogDia / 2 + 2 mm"
equation "d124 = MateWidth"
equation "d125 = LogDia / 2 + 2 mm"
equation "d126 = LogDia + 1 mm"
equation "d127 = L3_Length"
equation "d129 = L3_FirstNotch - NotchWidth / 2"
equation "d130 = LogDia / 2 - NotchDepth"
equation "d131 = L3_FirstNotch + NotchWidth / 2"
equation "d132 = LogDia / 2 + 2 mm"
equation "d133 = L3_FirstNotch - NotchWidth / 2"
equation "d134 = LogDia / 2 - NotchDepth"
equation "d135 = L3_FirstNotch + NotchWidth / 2"
equation "d136 = LogDia / 2 + 2 mm"
equation "d137 = LogDia + 2 mm"
equation "d139 = max(L3_Notches; 2)"
equation "d141 = L3_NotchStep"
equation "L4_Length = 10.625 in" comment "Overall length"
equation "L4_Notches = 4" comment "Number of notch positions"
equation "L4_FirstNotch = ( L4_Length - ( L4_Notches - 1 ) * NotchCenters ) / 2" comment "Centre of the first notch (keeps the row of notches centred)"
equation "L4_NotchStep = NotchCenters * min(1; L4_Notches - 1) + 0.001 mm * ( 1 - min(1; L4_Notches - 1) )" comment "Pattern step: NotchCenters, or about zero when there is only one notch"
equation "d147 = LogDia / 2 - PrintFlat / 2"
equation "d148 = LogDia"
equation "d149 = L4_Length"
equation "d152 = EndRadius"
equation "d153 = LogDia / 2 + 2 mm"
equation "d154 = PrintFlat"
equation "d155 = LogDia / 2 + 2 mm"
equation "d156 = LogDia / 2 + 2 mm"
equation "d157 = MateWidth"
equation "d158 = LogDia / 2 + 2 mm"
equation "d159 = LogDia + 1 mm"
equation "d160 = L4_Length"
equation "d162 = L4_FirstNotch - NotchWidth / 2"
equation "d163 = LogDia / 2 - NotchDepth"
equation "d164 = L4_FirstNotch + NotchWidth / 2"
equation "d165 = LogDia / 2 + 2 mm"
equation "d166 = L4_FirstNotch - NotchWidth / 2"
equation "d167 = LogDia / 2 - NotchDepth"
equation "d168 = L4_FirstNotch + NotchWidth / 2"
equation "d169 = LogDia / 2 + 2 mm"
equation "d170 = LogDia + 2 mm"
equation "d172 = max(L4_Notches; 2)"
equation "d174 = L4_NotchStep"
equation "Half2_Length = 4.5 in" comment "Overall length"
equation "Half2_Notches = 2" comment "Number of notch positions"
equation "Half2_FirstNotch = ( Half2_Length - ( Half2_Notches - 1 ) * NotchCenters ) / 2" comment "Centre of the first notch (keeps the row of notches centred)"
equation "Half2_NotchStep = NotchCenters * min(1; Half2_Notches - 1) + 0.001 mm * ( 1 - min(1; Half2_Notches - 1) )" comment "Pattern step: NotchCenters, or about zero when there is only one notch"
equation "d180 = LogDia"
equation "d181 = Half2_Length"
equation "d184 = EndRadius"
equation "d185 = LogDia / 2 + 2 mm"
equation "d186 = LogDia / 2 + 1 mm"
equation "d187 = LogDia / 2 + 2 mm"
equation "d188 = MateWidth / 2"
equation "d190 = LogDia / 2 + 2 mm"
equation "d191 = LogDia + 1 mm"
equation "d192 = MateWidth / 2"
equation "d194 = LogDia / 2 + 2 mm"
equation "d195 = LogDia + 1 mm"
equation "d196 = Half2_Length"
equation "d198 = Half2_FirstNotch - NotchWidth / 2"
equation "d199 = BaseLogHeight - NotchDepth"
equation "d200 = Half2_FirstNotch + NotchWidth / 2"
equation "d201 = BaseLogHeight + 1 mm"
equation "d202 = LogDia + 2 mm"
equation "d204 = max(Half2_Notches; 2)"
equation "d206 = Half2_NotchStep"
equation "Half3_Length = 7.5 in" comment "Overall length"
equation "Half3_Notches = 3" comment "Number of notch positions"
equation "Half3_FirstNotch = ( Half3_Length - ( Half3_Notches - 1 ) * NotchCenters ) / 2" comment "Centre of the first notch (keeps the row of notches centred)"
equation "Half3_NotchStep = NotchCenters * min(1; Half3_Notches - 1) + 0.001 mm * ( 1 - min(1; Half3_Notches - 1) )" comment "Pattern step: NotchCenters, or about zero when there is only one notch"
equation "d212 = LogDia"
equation "d213 = Half3_Length"
equation "d216 = EndRadius"
equation "d217 = LogDia / 2 + 2 mm"
equation "d218 = LogDia / 2 + 1 mm"
equation "d219 = LogDia / 2 + 2 mm"
equation "d220 = MateWidth / 2"
equation "d222 = LogDia / 2 + 2 mm"
equation "d223 = LogDia + 1 mm"
equation "d224 = MateWidth / 2"
equation "d226 = LogDia / 2 + 2 mm"
equation "d227 = LogDia + 1 mm"
equation "d228 = Half3_Length"
equation "d230 = Half3_FirstNotch - NotchWidth / 2"
equation "d231 = BaseLogHeight - NotchDepth"
equation "d232 = Half3_FirstNotch + NotchWidth / 2"
equation "d233 = BaseLogHeight + 1 mm"
equation "d234 = LogDia + 2 mm"
equation "d236 = max(Half3_Notches; 2)"
equation "d238 = Half3_NotchStep"
equation "Bev_Length = 1.5 in" comment "Length along the long edge"
equation "Bev_Angle = 39 deg" comment "Angle of the slanted end (roof pitch of the wooden triangle)"
equation "d242 = LogDia / 2 - PrintFlat / 2"
equation "d243 = LogDia"
equation "d244 = Bev_Length"
equation "d247 = EndRadius"
equation "d248 = LogDia / 2 + 2 mm"
equation "d249 = PrintFlat"
equation "d250 = LogDia / 2 + 2 mm"
equation "d251 = LogDia / 2 + 2 mm"
equation "d252 = MateWidth"
equation "d253 = LogDia / 2 + 2 mm"
equation "d254 = LogDia + 1 mm"
equation "d255 = Bev_Length"
equation "d257 = Bev_Length"
equation "d258 = LogDia / 2"
equation "d259 = LogDia / 2"
equation "d260 = Bev_Length - LogDia / tan(Bev_Angle)"
equation "d261 = LogDia + 2 mm"
equation "Solid1_Length = 1.375 in" comment "Length"
equation "d264 = LogDia / 2"
equation "d265 = LogDia / 2"
equation "d266 = LogDia"
equation "d267 = Solid1_Length"
equation "d270 = EndRadius"
equation "Solid2_Length = 1.625 in" comment "Length"
equation "d272 = LogDia / 2"
equation "d273 = LogDia / 2"
equation "d274 = LogDia"
equation "d275 = Solid2_Length"
equation "d278 = EndRadius"
named bodies: "log_1insert_1-5_8_rounded", "log_1insert_1-1_2_round_rounded", "log_2insert_4-1_2_rounded", "log_3insert_7-5_8_rounded", "log_4insert_10-5_8_rounded", "base_log_4-1_2_rounded", "base_log_7-1_2_rounded", "beveled_end_1-1_2_rounded", "solid_log_1-3_8_rounded", "solid_log_1-5_8_rounded"
